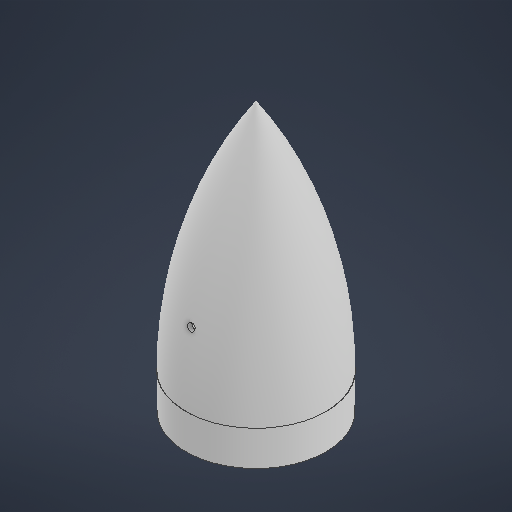
# Autodesk Inventor part: Nose Cone
Saved by Autodesk Inventor 2027 (Build 310192060, 192F)
## iProperties
Created: 2026-07-28
Part Number: Nose Cone
Material: PET Plastic
Document SubType Name: Modeling
Designer: troop
Density: 1.541 g/cm^3
Appearance: Default
Mass: 157.595 g
Surface Area: 483.477 cm^2
Volume: 102.268 cm^3
Author: troop
Autodesk Inventor part; units mm, degrees
ref_plane "YZ Plane" through (0, 0, 0) normal (1, 0, 0) x (0, 1, 0)
ref_plane "XZ Plane" through (0, 0, 0) normal (0, 1, 0) x (-1, 0, 0)
sketch "Sketch1" plane through (0, 0, 0) normal (0, 0, 1) x (1, 0, 0)
  line L0 (0, 0) -> (0, 127)
  line L1 (0, 0) -> (35.306, 0)
  arc A0 (38.1, 0) -> (0, 127) centre (-188.2356, 1.3143) ccw
  line L2 (37.9095, 0) -> (37.9095, -19.05)
  line L3 (0, 0) -> (0, 120.65)
  line L4 (0, 0) -> (38.1, 0)
  arc A1 (35.306, 0) -> (0, 120.65) centre (-169.4146, 5.5831) ccw
  line L5 (35.306, 0) -> (35.306, -19.05)
  line L6 (35.306, -19.05) -> (37.9095, -19.05)
  point P0 (0, 120.65)
  dimension "d0" = 127
  dimension "d1" = 35.306
  dimension "d2" = 226.3394
  dimension "d4" = 19.05
  dimension "d5" = 120.65
  dimension "d6" = 38.1
  dimension "d10" = 169.4146
  dimension "d11" = 188.2356
  dimension "d17" = 19.05
  dimension "d18" = 2.6035
  constraints: 13 end point, 4 point on circle, 4 vertical, 2 centre point, 2 horizontal, 2 point on line, 1 perpendicular
  measures "d0" distance of L0.start L0.end
  measures "d1" distance of L1.end L0.start
  measures "d2" radius of A0
  measures "d4" distance of L2.end L2.start
  measures "d5" distance of L0.start L3.end
  measures "d6" distance of L4.end L0.start
  measures "d10" horizontal distance of L0.start A1.centre
  measures "d11" horizontal distance of A0.centre L0.start
  measures "d17" distance of L1.end L5.end
  measures "d18" distance between parallel lines of L5 L2
revolve "Revolution1" add sketch "Sketch1" angle 360 about axis through (0, 0, 0) along (0, 1, 0) contours L0 A0 L4 A1 | L4 L2 L6 L5
ref_plane "Work Plane1" through (0, 0, 38.1) normal (0, 0, 1) x (1, 0, 0)
sketch "Sketch2" plane through (0, 0, 38.1) normal (0, 0, 1) x (1, 0, 0)
  circle A0 centre (0, 38.1) radius 2
  point P0 (0, 0)
  dimension "d20" = 4
  dimension "d21" = 38.1
  constraints: 1 centre point, 1 vertical alignment
  measures "d20" diameter of A0
  measures "d21" distance of point (0, 0) A0.centre
extrude "Extrusion1" cut sketch "Sketch2" against normal blind 25.4
body "Solid1"
